Bolt (Autodesk Fusion 360 design; units mm, degrees)
Autodesk Fusion 360 part; units mm, degrees
sketch "Sketch1" plane through (0, 0, 0) normal (0, 1, 0) x (1, 0, 0)
sketch "Sketch2" plane through (0, 0, 0) normal (0, 0, 1) x (1, 0, 0)
  circle A0 centre (0, 0) radius 5
  dimension "d1" = 10
  constraint coincident A0.centre origin
  measures "d1" diameter of A0
extrude "Extrude1" add sketch "Sketch2" along normal blind 40
sketch "Sketch3" plane through (0, 0, 40) normal (0, 0, 1) x (1, 0, 0)
  circle A0 centre (0, 0) radius 5
  line L0 (0, 0) -> (0, -8)
  line L1 (0, 0) -> (0, 8)
  line L2 (0, 0) -> (6.9282, 4)
  line L3 (0, 0) -> (6.9282, -4)
  line L4 (0, 0) -> (-6.9282, -4)
  line L5 (0, 0) -> (-6.9282, 4)
  line L6 (-9.2376, 0) -> (-4.6188, -8)
  line L7 (-4.6188, -8) -> (4.6188, -8)
  line L8 (4.6188, -8) -> (9.2319, -0.0099)
  line L9 (9.2319, -0.0099) -> (4.6188, 8)
  line L10 (4.6188, 8) -> (-4.6188, 8)
  line L11 (-4.6188, 8) -> (-9.2376, 0)
  constraint coincident A0.centre L0.start
  constraint parallel L3 L5
extrude "Extrude2" add sketch "Sketch3" along normal blind 8
thread "Thread1" "ISO Metric profile 10.0 M10x1.5 6g" major diameter 9.85 minor diameter 8.141 pitch 1.5 angle 60 modelled right hand crest width 0.1875 on face at (4.9938, -0.2492, 26.6667) crest through (4.925, 0, -0.0938)
chamfer "Chamfer1" distance 0.75 angle 45 6 edges at (0, 8, 48) (6.9253, 3.9951, 48) (6.9253, -4.0049, 48) (0, -8, 48) (-6.9282, -4, 48) (-6.9282, 4, 48) tangent chain off
chamfer "Chamfer2" distance 1 angle 45 6 edges at (6.9253, -4.0049, 40) (0, -8, 40) (-6.9282, 4, 40) (-6.9282, -4, 40) (0, 8, 40) (6.9253, 3.9951, 40) tangent chain off
